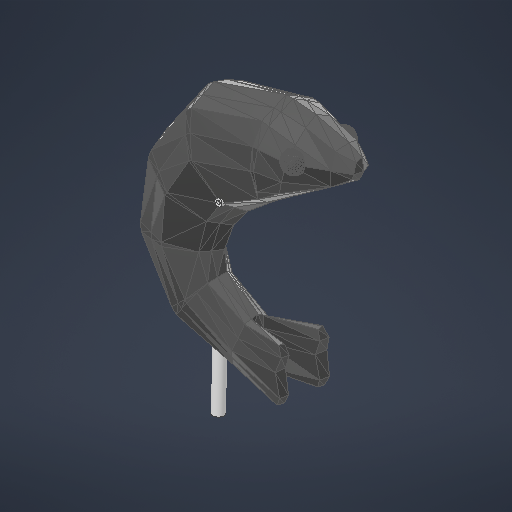
# Autodesk Inventor part: lowpolyshrimp
Saved by Autodesk Inventor 2026 (Build 300175050, 175E)
## iProperties
Created: 2025-05-12
Part Number: lowpolyshrimp
Material: Generic
Document SubType Name: Modeling
Designer: laura
Density: 1 g/cm^3
Appearance: Default
Author: laura
Autodesk Inventor part; units mm, degrees
ref_plane "YZ Plane" through (0, 0, 0) normal (1, 0, 0) x (0, 1, 0)
ref_plane "XZ Plane" through (0, 0, 0) normal (0, 1, 0) x (-1, 0, 0)
ref_plane "XY Plane" through (0, 0, 0) normal (0, 0, 1) x (1, 0, 0)
sketch "Sketch1" plane through (0, 0, 0) normal (0, 0, 1) x (1, 0, 0)
  line L0 (-0.0748, -2.9866) -> (-0.0748, -9.9866) construction
  circle A0 centre (-0.0748, -9.9866) radius 1.5
  point P0 (0, 0)
  dimension "d0" = 7
  dimension "d1" = 3
  constraints: 2 end point, 1 centre point, 1 coincident, 1 vertical
  measures "d0" distance of L0.start L0.end
  measures "d1" diameter of A0
extrude "Extrusion1" add sketch "Sketch1" along normal mid plane 20
sketch "Sketch2" plane through (0, 0, 0) normal (0, 0, 1) x (1, 0, 0)
  point P0 (0, 0)
sketch "Sketch3" plane through (0, 0, 0) normal (1, 0, 0) x (0, 1, 0)
  circle A0 centre (-5.0498, 41.0059) radius 0.5
  circle A1 centre (-5.0498, 41.0059) radius 1
  line L0 (-5.0498, 40.5059) -> (-5.0498, 41.0059)
  point P0 (0, 0)
  dimension "d4" = 1
  dimension "d5" = 2
  dimension "d8" = 0.5
  constraints: 2 centre point, 2 coincident, 2 end point, 1 vertical
  measures "d4" diameter of A0
  measures "d5" diameter of A1
  measures "d8" distance of L0.start L0.end
extrude "Extrusion2" add sketch "Sketch3" along normal mid plane 13.5
body "Solid1"
